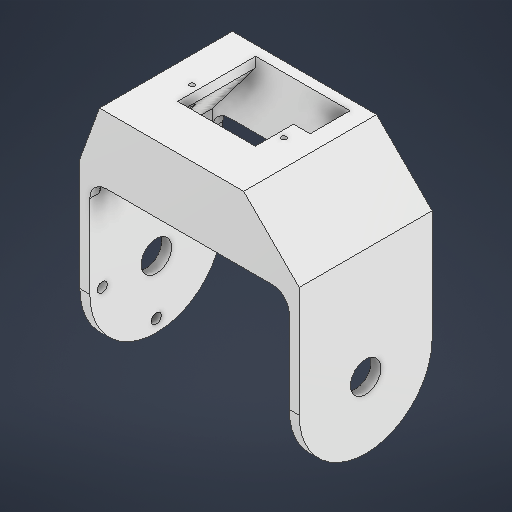
# Autodesk Inventor part: ranne
Saved by Autodesk Inventor 2026.1 (Build 301233020, 233B)
## iProperties
Created: 2025-10-07
Part Number: ranne
Material: ABS Plastic
Document SubType Name: Modeling
Designer: kuuse
Density: 1.06 g/cm^3
Appearance: Smooth - White
Author: kuuse
## iProperties of the stored document ranne_3DPrint.ipt
Created: 2025-11-05
Part Number: ranne_3DPrint
Material: Generic
Document SubType Name: Modeling
Designer: kuuse
Density: 1 g/cm^3
Appearance: Default
Author: kuuse
Autodesk Inventor part; units mm, degrees
ref_plane "YZ Plane" through (0, 0, 0) normal (1, 0, 0) x (0, 1, 0)
ref_plane "XZ Plane" through (0, 0, 0) normal (0, 1, 0) x (-1, 0, 0)
ref_plane "XY Plane" through (0, 0, 0) normal (0, 0, 1) x (1, 0, 0)
sketch "Sketch1" plane through (0, 0, 0) normal (0, 0, 1) x (1, 0, 0)
  line L0 (30, 30) -> (-30, 30)
  line L1 (-30, 30) -> (-30, -20)
  line L2 (-30, -20) -> (-40, -20)
  line L3 (-40, -20) -> (-40, 50)
  line L4 (-40, 50) -> (40, 50)
  line L5 (40, 50) -> (40, -20)
  line L6 (40, -20) -> (30, -20)
  line L7 (30, -20) -> (30, 30)
  line L8 (30, 0) -> (-30, 0) construction
  line L9 (0, 0) -> (0, 122.4827) construction
  line L10 (6.3, 30) -> (6.3, 50)
  line L11 (-17.1, 50) -> (-17.1, 30)
  line L12 (-17.1, 30) -> (-30, 30)
  line L13 (30, 30) -> (40, 30)
  line L14 (-17.1, 30) -> (-40, 30)
  line L15 (6.3, 47) -> (16.3, 47)
  line L16 (16.3, 47) -> (16.3, 33)
  line L17 (16.3, 33) -> (-17.1, 33)
  line L18 (-6.3, 30) -> (-6.3, 33)
  line L19 (-6.3, 33) -> (-6.3, 50)
  line L20 (16.3, 33) -> (16.3, 30)
  line L21 (-33, -20) -> (-33, 33.7899)
  line L22 (-33, 33.7899) -> (-27.1, 50)
  line L23 (33, 33.3) -> (16.3, 50)
  line L24 (33, -20) -> (33, 33.3)
  line L25 (-30, 30) -> (-17.1, 47)
  line L26 (30, 30) -> (16.3, 47)
  line L27 (6.3, 47) -> (-17.1, 47)
  point P0 (6.3, 33)
  dimension "d0" = 10
  dimension "d1" = 60
  dimension "d3" = 20
  dimension "d4" = 30
  dimension "d5" = 6.3
  dimension "d6" = 23.4
  dimension "d10" = 3
  dimension "d11" = 3
  dimension "d13" = 6.3
  dimension "d51" = 10
  dimension "d61" = 17
  dimension "d64" = 3
  dimension "d65" = 3
  dimension "d66" = 70
  dimension "d67" = 45
  dimension "d68" = 10
  dimension "d69" = 10
  dimension "d70" = 3
  constraints: 56 end point, 22 point on line, 14 perpendicular, 4 vertical, 2 horizontal, 1 coincident, 1 collinear, 1 midpoint
  measures "d0" distance between parallel lines of L5 L7
  measures "d1" distance between parallel lines of L1 L7
  measures "d3" distance between parallel lines of L8 L6
  measures "d4" distance between parallel lines of L0 L8
  measures "d5" distance between parallel lines of L10 L9
  measures "d6" distance between parallel lines of L10 L11
  measures "d10" distance of L10.end L15.start
  measures "d11" distance between parallel lines of L17 L0
  measures "d13" distance between parallel lines of L9 L19
  measures "d51" distance between parallel lines of L16 L10
  measures "d61" distance between parallel lines of L17 L4
  measures "d64" distance between parallel lines of L24 L7
  measures "d65" distance between parallel lines of L1 L21
  measures "d66" angle of L4 L22
  measures "d67" angle of L4 L23
  measures "d68" distance from line of L23.end L10
  measures "d69" distance of L11.start L22.end
  measures "d70" distance from line of L4 L25.end
extrude "Extrusion1" add sketch "Sketch1" along normal mid plane 40 contours L13 L24 L6 L7 | L26 L15 L10 L4 L23 L24 L13 | L0 L20 L16 L26 | L0 L10 L17 L20 | L16 L17 L10 L15 | L0 L18 L17 L10 | L27 L19 L4 L10 | L10 L17 L19 L27 | L0 L11 L17 L18 | L27 L11 L4 L19 | L19 L17 L11 L27 | L0 L25 L11 | L25 L14 L21 L22 L4 L11 | L1 L2 L21 L14
extrude "Extrusion2" cut sketch "Sketch1" along normal blind 6.5 and the other way blind 17 contours L16 L17 L10 L15 | L27 L19 L4 L10 | L10 L17 L19 L27 | L27 L11 L4 L19 | L19 L17 L11 L27
extrude "Extrusion3" cut sketch "Sketch1" along normal mid plane 34 contours L0 L20 L16 L26 | L0 L10 L17 L20 | L16 L17 L10 L15 | L0 L18 L17 L10 | L10 L17 L19 L27 | L0 L11 L17 L18 | L19 L17 L11 L27 | L0 L25 L11
fillet "Fillet1" radius 20 4 edges at (31.5, -20, 20) (31.5, -20, -20) (-31.5, -20, -20) (-31.5, -20, 20)
sketch "Sketch2" plane through (0, 0, 0) normal (1, 0, 0) x (0, 1, 0)
  arc A0 (0, 20) -> (0, -20) centre (0, 0) ccw construction
  line L0 (30, -20) -> (0, -20) construction
  line L1 (30, -20) -> (30, -17) construction
  line L2 (0, 20) -> (30, 20) construction
  circle A1 centre (0, 0) radius 4.6
  line L3 (0, 0) -> (16.25, 0)
  line L4 (0, 0) -> (0, 16.25)
  line L5 (0, 0) -> (-16.25, 0)
  line L6 (0, 0) -> (0, -16.25)
  circle A2 centre (0, -16.25) radius 1.5
  circle A3 centre (16.25, 0) radius 1.5
  circle A4 centre (0, 16.25) radius 1.5
  circle A5 centre (-16.25, 0) radius 1.5
  circle A6 centre (16.25, 0) radius 4
  circle A7 centre (0, 16.25) radius 4
  circle A8 centre (-16.25, 0) radius 4
  circle A9 centre (0, -16.25) radius 4
  line L7 (30, -17) -> (30, 17) projected
  line L8 (30, 17) -> (30, 20) projected
  point P0 (0, 0)
  dimension "d21" = 9.2
  dimension "d25" = 3
  dimension "d26" = 32.5
  dimension "d27" = 8
  constraints: 9 centre point, 9 coincident, 8 end point, 6 equal radius, 3 perpendicular, 2 horizontal, 2 vertical
  measures "d21" diameter of A1
  measures "d25" diameter of A5
  measures "d26" distance of L3.end L5.end
  measures "d27" diameter of A6
extrude "Extrusion4" cut sketch "Sketch2" along normal blind 53.75 contours L3 L4 A1 | A1 L6 L3 | L4 L5 A1 | A1 L5 L6
extrude "Extrusion9" cut sketch "Sketch2" against normal blind 3 from surface at -30 contours L3 L4 A1 | A1 L6 L3 | L4 L5 A1 | A1 L5 L6
extrude "Extrusion5" cut sketch "Sketch2" against normal blind 53.75 contours A2 | A5 | A4 | A3
sketch "Sketch3" plane through (-40, 50, -20) normal (0, 1, 0) x (1, 0, 0)
  line L0 (46.3, -3) -> (46.3, -26.5) projected
  line L1 (22.9, -26.5) -> (22.9, -3) projected
  line L2 (-6.2, -20) -> (86.2, -20) projected
  line L3 (46.3, -20) -> (48.4, -20)
  line L4 (22.9, -20) -> (20.8, -20)
  circle A0 centre (20.8, -20) radius 0.75
  circle A1 centre (48.4, -20) radius 0.75
  line L5 (33.7, -3) -> (22.9, -3) projected
  line L6 (46.3, -15) -> (51.3, -15)
  line L7 (51.3, -15) -> (51.3, -3)
  line L8 (51.3, -3) -> (46.3, -3)
  line L9 (56.3, -37) -> (33.7, -37) projected
  point P0 (40, -20)
  point P1 (46.3, -37)
  point P2 (22.9, -37)
  point P3 (56.3, -3)
  point P4 (46.3, -3)
  dimension "d52" = 27.6
  dimension "d53" = 1.5
  dimension "d59" = 5
  dimension "d60" = 5
  constraints: 10 end point, 7 point on line, 2 centre point, 2 coincident, 1 collinear, 1 equal radius, 1 horizontal, 1 perpendicular, 1 vertical, 3 other
  measures "d52" distance of L3.end L4.end
  measures "d53" diameter of A1
  measures "d59" distance of L6.start L6.end
  measures "d60" distance from line of L6 A1.centre
extrude "Extrusion7" cut sketch "Sketch3" against normal blind 13
fillet "Fillet3" radius 5 4 edges at (-30, 30, 18.5) (-30, 30, -18.5) (30, 30, -18.5) (30, 30, 18.5)
equation "\"d1\" = W1"
equation "\"d13\" = d5"
equation "\"W1\" = 60"
body "Solid1"
